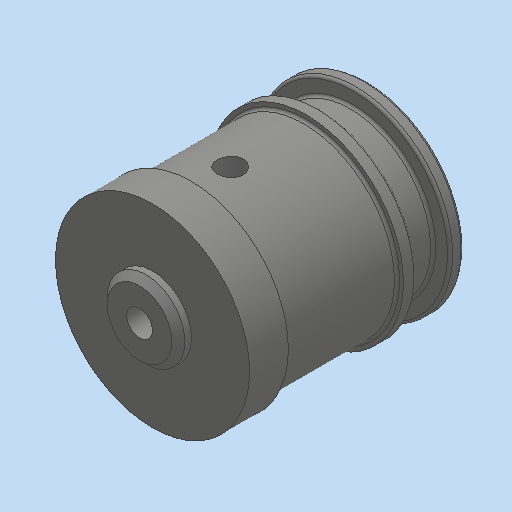
# Autodesk Inventor part: MM0948AN160_G01_110
Saved by Autodesk Inventor 2023.3 (Build 273359000, 359)
## iProperties
RuleStatus: InUse
BeforeDocSave0: file://AnP_Ansicht_ausrichten
Part Number: MM0948AN160_G01_110
Material: 1.2379 X155CrVMo12-1
Description: =<RBPARTNOTITLE2>
Document SubType Name: Modeling
Designer: ric7an
Mass: 20.3789 g
Surface Area: 13.6014 cm^2
Volume: 2.59604 cm^3
Density: 7.85 g/cm^3
Appearance: Stahl - rostfrei AnP
Created: 2023-03-23
RBDOCUMENTTYPE: DRF
RBDOCUMENTVERSION: 00
RBDRAWINGMAINSCALE: 1:1
RBDRAWINGMISSINGSPEC: --
RBDRAWINGVOLUME: --
RBGBEDGESIN1: +0,5
RBGBEDGESIN2: +0,2
RBGBEDGESOUT1: -0,3
RBGBEDGESOUT2: -0,1
RBMATERIAL: =<Material>
RBMATMEETS: --
RBMATNO: =<Part Number>
RBPARTMADEOF: Rd. 15 x 18 (FM)
RBPARTNO: SIEHE MNR
RBPARTNOTITLE1: manufactured part
RBPARTNOTITLE2: Anfertigungsteil
RBPARTSAFETYINDICATOR: --
RBSURFACE: vaccum hardened 61 HRC ± 1
RBSURFACE2: vakuumgehaertet 61 HRC ± 1
RBZEDGESNORM: ISO13715:2002-06
RBZGENDIMCLASS: m
RBZGENDIMNORM: ISO 2768-1:1989-11
RBZGENGEOCLASS: H
RBZGENGEONORM: ISO 2768-2:1989-11
RBZSURFACENORM: ISO13D2:2002-02
RBZTOLERANCENORM: ISO 14405-1:2010-12
AnP_Material: =<Material>
AnP_TemplVers: 20190222
AnP_Kategorie: 1
MaxAbmaße: 15 x 18 x 15 (FM)
AnP_Kommentar_aktuell: =<Comments>
AnP_Material_aktuell: =<Material>
Author: FH/Wi
Keywords: =<RBPARTMADEOF>
Comments: =<RBSURFACE2>
Revision Number: 01
Autodesk Inventor part; units mm, degrees
ref_plane "YZ Plane" through (0, 0, 0) normal (1, 0, 0) x (0, 1, 0)
ref_plane "XZ Plane" through (0, 0, 0) normal (0, 1, 0) x (-1, 0, 0)
sketch "Skizze1" plane through (0, 0, 0) normal (0, 0, 1) x (1, 0, 0)
  line L0 (0, 20.6) -> (0, -4.6) projected
  line L1 (0, 17) -> (-7.5, 17)
  line L2 (-7.5, 17) -> (-7.5, 0)
  line L3 (0, 0) -> (0, 17)
  line L4 (-7.5, 12.9) -> (-6.2, 12.9)
  line L5 (-6.2, 12.9) -> (-6.2, 15.5)
  line L6 (-6.2, 15.5) -> (-7.5, 15.5)
  line L7 (-7.5, 15.5) -> (-7.5, 12.9)
  line L8 (-7.5, 3.0183) -> (-7.5, 5.6183)
  line L9 (-7.5, 3) -> (-7, 3)
  line L10 (-7, 3) -> (-7, 11.9)
  line L11 (-7, 11.9) -> (-7.5, 11.9)
  line L12 (-7.5, 11.9) -> (-7.5, 3)
  line L13 (0, 17) -> (-4, 17)
  line L14 (-7.5, 0) -> (0, 0)
  line L15 (-9, 0) -> (1.5, 0) projected
  line L16 (0, 0) -> (-3, 0)
  line L17 (-3, 0) -> (-3, -1)
  line L18 (-3, -1) -> (0, -1)
  line L19 (0, -1) -> (0, 0)
  dimension "d5" = 2.6
  dimension "d6" = 1.5
  dimension "d7" = 1
  dimension "d9" = 0.5
  dimension "d10" = 7.5
  dimension "d24" = 3
  dimension "d25" = 17
  dimension "d26" = 1.3
  dimension "d27" = 1
  dimension "d28" = 3
  constraints: 36 end point, 7 parallel, 5 horizontal, 4 perpendicular, 4 point on line, 1 collinear
  measures "d5" distance of L4.end L5.end
  measures "d6" distance between parallel lines of L1 L6
  measures "d7" distance between parallel lines of L4 L11
  measures "d9" distance between parallel lines of L12 L10
  measures "d10" distance of L2.end L3.start
  measures "d24" distance between parallel lines of L15 L9
  measures "d25" distance between parallel lines of L15 L1
  measures "d26" distance between parallel lines of L5 L2
  measures "d27" distance of L16.end L17.end
  measures "d28" distance of L17.end L18.end
revolve "Umdrehung1" add sketch "Skizze1" angle 360 about axis through (0, 0, 0) along (0, -1, 0) contours L0 L14 L2 L9 L10 L11 L4 L5 L6 L1 | L0 L18 L17 L14
chamfer "Fase1" distance 1.4 angle 20 1 edges at (7.5, 17, 0) measured on face at (2.556, 17, 1.6578)
fillet "Rundung1" radius 0.2 7 edges at (7.5, 15.5, 0) (7.5, 12.9, 0) (6.2, 15.5, 0) (6.2, 12.9, 0) (7.5, 16.4904, 0) (7, 11.9, 0) (7, 3, 0)
chamfer "Fase2" distance 0.5 angle 45 1 edges at (3, -1, 0)
hole "Bohrung1" at (0, -1, 0) direction (0, 1, 0) diameter 2 depth 10 tip angle 118
ref_plane "Arbeitsebene1" through (0, 7.45, -7) normal (0, 0, 1) x (1, 0, 0)
sketch "Skizze4" plane through (0, 7.45, -7) normal (0, 0, 1) x (1, 0, 0)
  line L0 (0, 13.15) -> (0, -12.05) projected
  line L1 (-10.5, -7.45) -> (10.5, -7.45) projected
  point P0 (0, -7.45)
  point P1 (0, -1.45)
  dimension "d41" = 6
  constraints: 1 point on line
  measures "d41" distance from line of L1 point (0, -1.45)
hole "Bohrung2" at (0, 6, -7) direction (0, 0, 1) diameter 2 end through all
equation "\"d5\" = d4"
equation "\"d4\" = 2.6"
